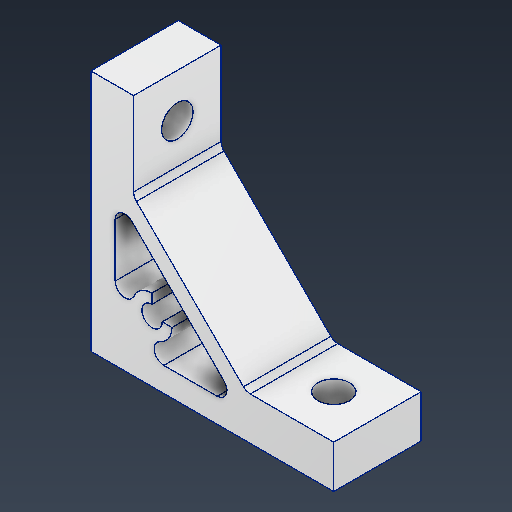
# Autodesk Inventor part: 2020 Angle Corner Brecket
Saved by Autodesk Inventor 2026.2 (Build 302298010, 298A)
## iProperties
Created: 2026-05-13
Part Number: 2020 Angle Corner Brecket
Material: 알루미늄 6061
Document SubType Name: Modeling
Designer: khw
Density: 2.7 g/cm^3
Appearance: 알루미늄 - 평지
Author: khw
Autodesk Inventor part; units mm, degrees
ref_plane "YZ Plane" through (0, 0, 0) normal (1, 0, 0) x (0, 1, 0)
ref_plane "XZ Plane" through (0, 0, 0) normal (0, 1, 0) x (-1, 0, 0)
ref_plane "XY Plane" through (0, 0, 0) normal (0, 0, 1) x (1, 0, 0)
sketch "스케치1" plane through (0, 0, 0) normal (0, 0, 1) x (1, 0, 0)
  line L0 (0, 0) -> (50, 0)
  line L1 (50, 0) -> (50, 50)
  line L2 (50, 50) -> (0, 50)
  line L3 (0, 50) -> (0, 0)
  line L4 (50, 50) -> (8.8, 50)
  line L5 (8.8, 50) -> (8.8, 8.8) construction
  line L6 (8.8, 8.8) -> (50, 8.8) construction
  line L7 (50, 8.8) -> (50, 50)
  line L8 (8.8, 32) -> (32, 8.8)
  line L9 (8.8, 27.0503) -> (27.0503, 8.8)
  line L10 (27.0503, 8.8) -> (30.8503, 5)
  line L11 (30.8503, 5) -> (5, 5)
  line L12 (5, 5) -> (5, 30.8503)
  line L13 (5, 30.8503) -> (8.8, 27.0503)
  line L14 (0, 0) -> (20.4, 20.4) construction
  circle A0 centre (12.6, 12.6) radius 2.1
  circle A1 centre (12.6, 12.6) radius 4.1
  line L15 (5, 5) -> (12.6, 5)
  line L16 (12.6, 5) -> (12.6, 12.6)
  line L17 (12.6, 12.6) -> (5, 12.6)
  line L18 (5, 12.6) -> (5, 5)
  line L19 (50, 8.8) -> (32, 8.8)
  line L20 (8.8, 32) -> (8.8, 50)
  line L21 (12.6, 12.6) -> (17.9251, 12.6)
  line L22 (17.9251, 12.6) -> (17.9251, 17.9251)
  line L23 (17.9251, 17.9251) -> (12.6, 17.9251)
  line L24 (12.6, 17.9251) -> (12.6, 12.6)
  point P0 (25, 0)
  point P1 (41, 8.8)
  point P2 (12.6, 8.5)
  point P3 (16.7, 12.6)
  point P4 (14.7, 12.6)
  point P5 (12.6, 14.7)
  point P6 (12.6, 16.7)
  point P7 (8.5, 12.6)
  point P8 (5, 12.6)
  dimension "d0" = 50
  dimension "d1" = 50
  dimension "d2" = 8.8
  dimension "d3" = 8.8
  dimension "d4" = 45
  dimension "d5" = 3.5
  dimension "d6" = 5
  dimension "d7" = 5
  dimension "d8" = 4.2
  dimension "d9" = 41
  dimension "d10" = 9
  dimension "d11" = 2
  dimension "d12" = 3.8
  constraints: 50 end point, 9 parallel, 9 point on line, 6 perpendicular, 5 horizontal, 3 midpoint, 2 centre point, 2 collinear, 1 coincident
  measures "d0" distance of L2.end L1.end
  measures "d1" distance of L1.end L0.end
  measures "d2" distance between parallel lines of L3 L5
  measures "d3" distance between parallel lines of L0 L6
  measures "d4" angle of L6 L9
  measures "d5" distance between parallel lines of L8 L9
  measures "d6" distance from line of point (25, 0) L11
  measures "d7" distance between parallel lines of L3 L12
  measures "d8" diameter of A0
  measures "d9" distance from line of L3 point (41, 8.8)
  measures "d10" distance of L8.end point (41, 8.8)
  measures "d11" radial gap between concentric circles of A1 A0
  measures "d12" distance from line of A0.centre L6
extrude "돌출1" add sketch "스케치1" along normal blind 18 contours L3 L2 L20 L8 L19 L1 L0 | L17 A1 L16 L11 L12 | A1 L16 A0 L21 | L24 A0 L17 A1 | L17 A0 L16 A1
fillet "모깎기1" radius 2 8 edges at (12.6, 5, 9) (12.6, 8.5, 9) (8.5, 12.6, 9) (5, 12.6, 9) (5, 30.8503, 9) (30.8503, 5, 9) (32, 8.8, 9) (8.8, 32, 9)
sketch "스케치2" plane through (50, 8.8, 18) normal (0, 1, 0) x (1, 0, 0)
  line L0 (0, 18) -> (0, 0) projected
  line L1 (0, 9) -> (-50, 9) construction
  line L2 (-50, 18) -> (-50, 0) projected
  circle A0 centre (-9, 9) radius 3.25
  dimension "d16" = 6.5
  dimension "d17" = 41
  constraints: 2 end point, 2 midpoint, 1 centre point, 1 coincident, 1 point on line
  measures "d16" diameter of A0
  measures "d17" distance from line of L2 A0.centre
extrude "돌출2" cut sketch "스케치2" against normal through all
sketch "스케치3" plane through (8.8, 50, 18) normal (1, 0, 0) x (0, 0, -1)
  line L0 (18, 0) -> (0, 0) projected
  line L1 (9, 0) -> (9, -50) construction
  line L2 (12.25, -50) -> (5.75, -50) projected
  circle A0 centre (9, -9) radius 3.25
  line L3 (18, -50) -> (0, -50) projected
  dimension "d20" = 6.5
  dimension "d21" = 41
  constraints: 2 end point, 2 midpoint, 1 centre point, 1 point on line
  measures "d20" diameter of A0
  measures "d21" distance from line of L3 A0.centre
extrude "돌출3" cut sketch "스케치3" against normal through all
